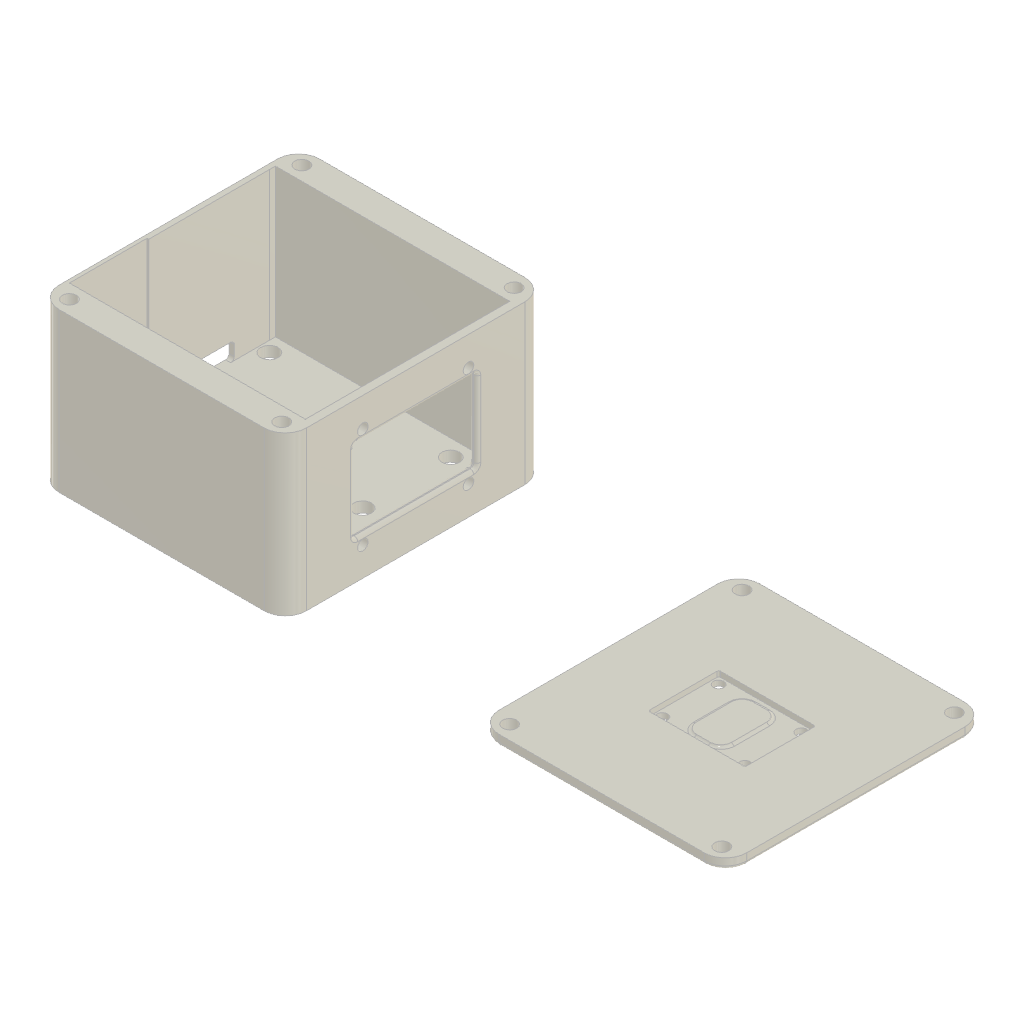
desktop_pet_housing (Autodesk Fusion 360 design; units mm, degrees)
part number: 2026-10-13-15-29-51-943
Autodesk Fusion 360 part; units mm, degrees
sketch "Sketch1" plane through (0, 0, 0) normal (0, 0, 1) x (1, 0, 0)
  line L0 (49.9787, 99.2431) -> (107.4787, 99.2431)
  line L1 (107.4787, 99.2431) -> (107.4787, 68.2431)
  line L2 (107.4787, 68.2431) -> (49.9787, 68.2431)
  line L3 (49.9787, 68.2431) -> (49.9787, 99.2431)
  line L4 (49.9787, 99.2431) -> (49.9787, 96.2431) construction
  line L5 (49.9787, 96.2431) -> (52.9787, 96.2431) construction
  line L6 (49.9787, 68.2431) -> (52.9787, 68.2431) construction
  line L7 (52.9787, 68.2431) -> (52.9787, 71.2431) construction
  line L8 (107.4787, 68.2431) -> (107.4787, 71.2431) construction
  line L9 (107.4787, 71.2431) -> (104.4787, 71.2431) construction
  line L10 (107.4787, 99.2431) -> (107.4787, 96.2431) construction
  line L11 (107.4787, 96.2431) -> (104.4787, 96.2431) construction
  circle A0 centre (52.9787, 96.2431) radius 2.5
  circle A1 centre (52.9787, 71.2431) radius 2.5
  circle A2 centre (104.4787, 71.2431) radius 2.5
  circle A3 centre (104.4787, 96.2431) radius 2.5
  line L12 (51.4787, 78.7555) -> (48.4787, 78.7555)
  line L13 (48.4787, 78.7555) -> (48.4787, 89.2555)
  line L14 (48.4787, 89.2555) -> (51.4787, 89.2555)
  line L15 (51.4787, 89.2555) -> (51.4787, 78.7555)
  line L16 (51.4787, 78.7555) -> (48.4787, 89.2555) construction
  line L17 (48.4787, 78.7555) -> (51.4787, 89.2555) construction
  line L18 (52.9787, 71.2431) -> (49.9787, 71.2431) construction
  line L19 (52.9787, 96.2431) -> (52.9787, 99.2431) construction
  line L20 (104.4787, 71.2431) -> (104.4787, 68.2431) construction
  line L21 (104.4787, 96.2431) -> (104.4787, 99.2431) construction
  line L22 (61.5, 44) -> (49.5, 44)
  line L23 (61.5, 65) -> (61.5, 44)
  circle A4 centre (51.5, 46) radius 1.6
  line L24 (50.5, 50.75) -> (50.5, 59.25)
  circle A5 centre (51.5, 63) radius 1.6
  line L25 (49.5, 65) -> (61.5, 65)
  line L26 (50.5, 59.25) -> (48.5, 59.25)
  line L27 (48.5, 50.75) -> (50.5, 50.75)
  line L28 (49.5, 44) -> (49.5, 65)
  line L29 (48.5, 50.75) -> (48.5, 59.25)
  line L30 (51.5, 46) -> (51.5, 44) construction
  line L31 (51.5, 46) -> (49.5, 46) construction
  line L32 (51.5, 63) -> (51.5, 65) construction
  line L33 (51.5, 63) -> (49.5, 63) construction
  line L34 (107.5, 65) -> (65.5, 65)
  line L35 (65.5, 65) -> (65.5, 45)
  line L36 (65.5, 45) -> (107.5, 45)
  line L37 (107.5, 45) -> (107.5, 65)
  line L38 (65.5, 65) -> (75.5, 65) construction
  circle A6 centre (75.5, 65) radius 1.5
  line L39 (75.5, 65) -> (75.5, 45) construction
  circle A7 centre (75.5, 45) radius 1.5
  line L40 (48.5, 42.9562) -> (116.5, 42.9562)
  line L41 (116.5, 42.9562) -> (116.5, 100.9562)
  line L42 (116.5, 100.9562) -> (48.5, 100.9562)
  line L43 (48.5, 100.9562) -> (48.5, 42.9562)
  line L44 (116.5, 42.9562) -> (113.7862, 42.9562) construction
  line L45 (48.5, 42.9562) -> (53.5, 42.9562) construction
  line L46 (116.5, 42.9562) -> (113.7862, 42.9562) construction
  line L47 (116.5, 100.9562) -> (113.7862, 100.9562) construction
  line L48 (48.5, 100.9562) -> (53.5, 100.9562) construction
  line L49 (113.7862, 42.9562) -> (113.7862, 38.9562) construction
  line L50 (53.5, 42.9562) -> (53.5, 38.9562) construction
  line L51 (53.5, 100.9562) -> (53.5, 104.9562) construction
  line L52 (113.7862, 100.9562) -> (113.7862, 104.9562) construction
  circle A8 centre (113.7862, 104.9562) radius 2
  circle A9 centre (53.5, 104.9562) radius 2
  circle A10 centre (53.5, 38.9562) radius 2
  circle A11 centre (113.7862, 38.9562) radius 2
  line L53 (48.5, 34.9615) -> (118.7862, 34.9615)
  line L54 (118.7862, 34.9615) -> (118.7862, 109)
  line L55 (118.7862, 109) -> (48.5, 109)
  line L56 (48.5, 109) -> (48.5, 34.9615)
  line L57 (173.5, 42.9562) -> (178.5, 42.9562) construction
  circle A12 centre (178.5, 38.9562) radius 2
  line L58 (178.5, 100.9562) -> (178.5, 104.9562) construction
  line L59 (233.5, 42.9562) -> (233.5, 100.9562)
  line L60 (178.5, 42.9562) -> (178.5, 38.9562) construction
  line L61 (243.786, 109) -> (173.5, 109)
  line L62 (233.5, 100.9562) -> (238.786, 100.9562) construction
  circle A13 centre (178.5, 104.9562) radius 2
  line L63 (173.5, 100.9562) -> (178.5, 100.9562) construction
  line L64 (173.5, 100.9562) -> (173.5, 42.9562)
  line L65 (173.5, 109) -> (173.5, 34.9615)
  line L66 (233.5, 100.9562) -> (173.5, 100.9562)
  line L67 (238.786, 100.9562) -> (238.786, 104.9562) construction
  line L68 (173.5, 34.9615) -> (243.786, 34.9615)
  circle A14 centre (238.786, 104.9562) radius 2
  line L69 (228.5, 42.9562) -> (228.5, 38.9562) construction
  line L70 (173.5, 42.9562) -> (233.5, 42.9562)
  line L71 (243.786, 34.9615) -> (243.786, 109)
  line L72 (233.5, 42.9562) -> (228.5, 42.9562) construction
  line L73 (233.5, 42.9562) -> (228.5, 42.9562) construction
  line L74 (243.786, 34.9615) -> (243.786, 71.9807) construction
  line L75 (243.786, 71.9807) -> (208.6431, 71.9156) construction
  line L76 (194.8931, 81.9156) -> (222.3931, 81.9156)
  line L77 (222.3931, 81.9156) -> (222.3931, 61.9156)
  line L78 (222.3931, 61.9156) -> (194.8931, 61.9156)
  line L79 (194.8931, 61.9156) -> (194.8931, 81.9156)
  line L80 (194.8931, 81.9156) -> (222.3931, 61.9156) construction
  line L81 (222.3931, 81.9156) -> (194.8931, 61.9156) construction
  line L82 (194.8931, 81.9156) -> (194.8931, 79.9156) construction
  line L83 (194.8931, 79.9156) -> (196.8931, 79.9156) construction
  line L84 (194.8931, 61.9156) -> (194.8931, 63.9156) construction
  line L85 (194.8931, 63.9156) -> (196.8931, 63.9156) construction
  line L86 (222.3931, 81.9156) -> (220.3931, 81.9156) construction
  line L87 (220.3931, 81.9156) -> (220.3931, 79.9156) construction
  line L88 (222.3931, 61.9156) -> (212, 61.9156) construction
  line L89 (222.3931, 61.9156) -> (222.3931, 63.9156) construction
  line L90 (222.3931, 63.9156) -> (220.3931, 63.9156) construction
  circle A15 centre (220.3931, 63.9156) radius 1.5
  circle A16 centre (220.3931, 79.9156) radius 1.5
  circle A17 centre (196.8931, 79.9156) radius 1.5
  circle A18 centre (196.8931, 63.9156) radius 1.5
  line L91 (203.4731, 63.9963) -> (213.4731, 63.9963)
  line L92 (213.4731, 63.9963) -> (213.4731, 79.9963)
  line L93 (213.4731, 79.9963) -> (203.4731, 79.9963)
  line L94 (203.4731, 79.9963) -> (203.4731, 63.9963)
  line L95 (49.9787, 99.2431) -> (49.9792, 100.9562)
  line L96 (49.9787, 68.2431) -> (49.9787, 65)
  line L97 (49.5, 44) -> (49.5, 42.9561)
  line L98 (113.7862, 38.9562) -> (118.7862, 38.9562) construction
  line L99 (113.7862, 104.9562) -> (118.7862, 104.9562) construction
  line L100 (228.5, 38.9562) -> (243.786, 38.9498) construction
  line L101 (238.786, 104.9562) -> (243.786, 104.9562) construction
  line L102 (238.786, 104.9562) -> (238.7585, 38.9519) construction
  circle A19 centre (238.7585, 38.9519) radius 2
  line L103 (49.9787, 68.2431) -> (49.9787, 83.7431) construction
  point P0 (49.9787, 84.0055)
  point P1 (208.6431, 71.9156)
  dimension "d1" = 57.5
  dimension "d2" = 31
  dimension "d10" = 3
  dimension "d14" = 5
  dimension "d15" = 3
  dimension "d16" = 10.5
  dimension "d17" = 12
  dimension "d18" = 21
  dimension "d20" = 3.2
  dimension "d21" = 2
  dimension "d22" = 8.5
  dimension "d23" = 2
  dimension "d31" = 42
  dimension "d32" = 20
  dimension "d33" = 10
  dimension "d34" = 3
  dimension "d35" = 3
  dimension "d36" = 68
  dimension "d37" = 58
  dimension "d39" = 5
  dimension "d41" = 5
  dimension "d42" = 4
  dimension "d43" = 4
  dimension "d44" = 4
  dimension "d45" = 4
  dimension "d46" = 4
  dimension "d47" = 4
  dimension "d48" = 4
  dimension "d49" = 4
  dimension "d67" = 60
  dimension "d68" = 58
  dimension "d70" = 5
  dimension "d72" = 5
  dimension "d73" = 4
  dimension "d74" = 4
  dimension "d75" = 4
  dimension "d76" = 4
  dimension "d77" = 4
  dimension "d78" = 4
  dimension "d79" = 4
  dimension "d81" = 74.0385
  dimension "d82" = 27.5
  dimension "d83" = 20
  dimension "d84" = 2
  dimension "d85" = 2
  dimension "d86" = 2
  dimension "d87" = 2
  dimension "d88" = 2
  dimension "d89" = 2
  dimension "d90" = 3
  dimension "d91" = 3
  dimension "d92" = 3
  dimension "d93" = 3
  dimension "d150" = 35.143
  dimension "d151" = 70.286
  dimension "d152" = 2
  dimension "d153" = 2
  dimension "d154" = 16
  dimension "d155" = 10
  dimension "d156" = 5
  dimension "d157" = 5
  dimension "d158" = 70.2862
  dimension "d159" = 74.0385
  dimension "d160" = 5
  dimension "d161" = 15.286
  dimension "d162" = 4
  dimension "d163" = 3
  dimension "d164" = 3
  dimension "d165" = 3
  constraint horizontal L0
  constraint vertical L1
  constraint horizontal L2
  constraint vertical L3
  constraint perpendicular L0 L4
  constraint perpendicular L3 L5
  constraint perpendicular L3 L6
  constraint perpendicular L6 L7
  constraint perpendicular L2 L8
  constraint perpendicular L1 L9
  constraint coincident L1 L10.end
  constraint perpendicular L10 L11
  constraint coincident L5.end A0.centre
  constraint coincident L7.end A1.centre
  constraint coincident L9.end A2.centre
  constraint coincident L11.end A3.centre
  constraint horizontal L12
  constraint perpendicular L12 L13
  constraint parallel L12 L14
  constraint parallel L13 L15
  constraint coincident L16 P0
  constraint coincident L17 P0
  constraint coincident L3 P0
  constraint equal A2 A3
  constraint equal A0 A3
  constraint equal A0 A1
  constraint coincident L3 L18.end
  constraint perpendicular L3 L18
  constraint coincident L0 L19.end
  constraint perpendicular L0 L19
  constraint coincident L2 L20.end
  constraint perpendicular L2 L20
  constraint coincident L0 L21.end
  constraint perpendicular L0 L21
  constraint equal L11 L21
  constraint equal L9 L20
  constraint equal L7 L18
  constraint equal L5 L19
  constraint perpendicular L24 L27
  constraint parallel L26 L27
  constraint perpendicular L26 L29
  constraint coincident A4.centre L30.start
  constraint coincident L22 L30.end
  constraint perpendicular L22 L30
  constraint coincident L28 L31.end
  constraint perpendicular L28 L31
  constraint coincident A5.centre L32.start
  constraint coincident L25 L32.end
  constraint perpendicular L25 L32
  constraint coincident L28 L33.end
  constraint perpendicular L28 L33
  constraint equal A4 A5
  constraint equal L32 L33
  constraint equal L30 L31
  constraint horizontal L34
  constraint vertical L35
  constraint horizontal L36
  constraint vertical L37
  constraint perpendicular L35 L38
  constraint coincident L38.end A6.centre
  constraint coincident L36 L39.end
  constraint perpendicular L36 L39
  constraint coincident L39.end A7.centre
  constraint horizontal L40
  constraint vertical L41
  constraint horizontal L42
  constraint vertical L43
  constraint coincident L40 L44.end
  constraint coincident L40 L45.end
  constraint coincident L42 L47.end
  constraint coincident L42 L48.end
  constraint perpendicular L46 L49
  constraint perpendicular L45 L50
  constraint perpendicular L42 L51
  constraint perpendicular L47 L52
  constraint coincident L52.end A8.centre
  constraint coincident L51.end A9.centre
  constraint coincident L50.end A10.centre
  constraint coincident L49.end A11.centre
  constraint horizontal L53
  constraint vertical L54
  constraint horizontal L55
  constraint vertical L56
  constraint horizontal L70
  constraint vertical L59
  constraint horizontal L66
  constraint vertical L64
  constraint coincident L69.start L70
  constraint coincident L57.end L70
  constraint coincident L62.end L66
  constraint coincident L58.start L66
  constraint perpendicular L69 L73
  constraint perpendicular L57 L60
  constraint perpendicular L58 L66
  constraint perpendicular L62 L67
  constraint coincident L67.end A14.centre
  constraint coincident L58.end A13.centre
  constraint coincident A12.centre L60.end
  constraint horizontal L68
  constraint vertical L71
  constraint horizontal L61
  constraint vertical L65
  constraint midpoint L71 L74.end
  constraint horizontal L76
  constraint perpendicular L76 L77
  constraint parallel L76 L78
  constraint parallel L77 L79
  constraint coincident L80 P1
  constraint coincident L81 P1
  constraint coincident P1 L75.end
  constraint perpendicular L76 L82
  constraint perpendicular L82 L83
  constraint coincident L79 L84.end
  constraint perpendicular L79 L85
  constraint coincident L76 L86.end
  constraint perpendicular L86 L87
  constraint coincident L78 L88.end
  constraint coincident L77 L89.end
  constraint perpendicular L77 L90
  constraint coincident L90.end A15.centre
  constraint coincident L87.end A16.centre
  constraint coincident L83.end A17.centre
  constraint coincident L85.end A18.centre
  constraint horizontal L91
  constraint vertical L92
  constraint horizontal L93
  constraint vertical L94
  constraint coincident L48 L95.end
  constraint coincident L25 L96.end
  constraint perpendicular L25 L96
  constraint vertical L97
  constraint coincident L54 L98.end
  constraint perpendicular L54 L98
  constraint coincident L54 L99.end
  constraint perpendicular L54 L99
  constraint coincident L74 L100.end
  constraint coincident L71 L101.end
  constraint perpendicular L71 L101
  constraint coincident L100 L102.end
  constraint perpendicular L100 L102
  constraint coincident L102.end A19.centre
  constraint midpoint L3 L103.end
  measures "d1" distance of L0.start L0.end
  measures "d2" distance of L0.start L2.end
  measures "d10" distance of L0.end L10.end
  measures "d14" diameter of A3
  measures "d15" distance of L13.end L14.end
  measures "d16" distance of L12.end L13.end
  measures "d17" distance of L22.start L22.end
  measures "d18" distance of L22.start L23.start
  measures "d20" diameter of A5
  measures "d21" distance of L24.end L26.end
  measures "d22" distance of L24.start L24.end
  measures "d23" distance of A5.centre L32.end
  measures "d31" distance of L34.start L34.end
  measures "d32" distance of L34.start L36.end
  measures "d33" distance of L34.end L38.end
  measures "d34" diameter of A6
  measures "d35" diameter of A7
  measures "d36" distance of L40.start L40.end
  measures "d37" distance of L40.start L42.end
  measures "d39" distance of L40.start L45.end
  measures "d41" distance of L42.end L48.end
  measures "d42" distance of L44.end L49.end
  measures "d43" distance of L45.end L50.end
  measures "d44" distance of L48.end L51.end
  measures "d45" distance of L47.end L52.end
  measures "d46" diameter of A8
  measures "d47" diameter of A9
  measures "d48" diameter of A10
  measures "d49" diameter of A11
  measures "d67" distance of L57.start L59.start
  measures "d68" distance of L63.start L57.start
  measures "d70" distance of L57.start L57.end
  measures "d72" distance of L63.start L58.start
  measures "d73" distance of L69.start L69.end
  measures "d74" distance of L57.end A12.centre
  measures "d75" distance of L58.start L58.end
  measures "d76" distance of L62.end L67.end
  measures "d77" diameter of A14
  measures "d78" diameter of A13
  measures "d79" diameter of A12
  measures "d81" distance of L61.start L68.end
  measures "d82" distance of L77.end L78.end
  measures "d83" distance of L76.end L77.end
  measures "d84" distance of L76.start L82.end
  measures "d85" distance of L78.end L84.end
  measures "d86" distance of L84.end L85.end
  measures "d87" distance of L76.end L86.end
  measures "d88" distance of L86.end L87.end
  measures "d89" distance of L77.end L89.end
  measures "d90" diameter of A15
  measures "d91" diameter of A16
  measures "d92" diameter of A17
  measures "d93" diameter of A18
  measures "d150" distance of L74.end P1
  measures "d151" distance of L65.end L68.end
  measures "d152" distance of L82.end L83.end
  measures "d153" distance of L89.end L90.end
  measures "d154" distance of L91.start L93.end
  measures "d155" distance of L92.end L93.end
  measures "d156" distance of L49.end L98.end
  measures "d157" distance of L52.end L99.end
  measures "d158" distance of L54.end L55.end
  measures "d159" distance of L53.end L54.end
  measures "d160" distance of L67.end L101.end
  measures "d161" horizontal distance of L69.end L100.end
  measures "d162" diameter of A19
  measures "d163" distance of L7.end L18.end
  measures "d164" distance of L5.end L19.end
  measures "d165" distance of L9.end L20.end
extrude "Extrude1" add sketch "Sketch1" along normal blind 45 contours L3 L14 L42 L43 L56 L95 | L40 L41 L42 L53 L54 L55 L56 | L3 L12 L25 L26 L28 L43 L56 L96 | L27 L28 L40 L43 L56 L97 makes body 1 at (118.7862, 59.641, 30) makes body 2 at (48.5, 72.2537, 15)
extrude "Extrude2" add sketch "Sketch1" along normal blind 3 contours L0 L1 L2 L22 L23 L25 L40 L41 L42 L95 L96 L97 | L0 L1 L2 L3 L12 L14 L15 | L3 L12 L14 L15 | L3 L12 L14 L43 L56 | L22 L23 L24 L25 L26 L27 L28 | L26 L27 L28 L29 L43 L56 | L24 L26 L27 L28 | L34 L35 L36 L37 A6 A7 bodies 1 2
extrude "Extrude3" add sketch "Sketch1" along normal blind 3 contours L26 L27 L28 L29 L43 L56 bodies 1
extrude "Extrude4" add sketch "Sketch1" along normal blind 37 from surface at 8 contours L26 L27 L28 L29 L43 L56 bodies 1
extrude "Extrude5" add sketch "Sketch1" along normal blind 37 from surface at 8 contours L3 L12 L14 L43 L56 | L12 L13 L14 L43 L56 bodies 1
extrude "Extrude6" add sketch "Sketch1" along normal blind 3 separate body contours L59 L64 L65 L66 L70 | L59 L61 L65 L66 L68 L70 L71 makes body 3
extrude "Extrude7" add sketch "Sketch1" along normal blind 1.5 and the other way blind 0 contours L76 L77 L78 L79 bodies 3
extrude "Extrude8" add sketch "Sketch1" along normal blind 2 contours L91 L92 L93 L94 bodies 3
sketch "Sketch2" plane through (118.7862, 0, 0) normal (1, 0, 0) x (0, 1, 0)
  line L0 (34.9615, 0) -> (109, 0)
  line L1 (109, 0) -> (109, 45)
  line L2 (109, 45) -> (34.9615, 45)
  line L3 (34.9615, 45) -> (34.9615, 0)
  line L4 (34.9615, 45) -> (109, 0) construction
  line L5 (34.9615, 0) -> (109, 45) construction
  line L6 (89.4807, 5.75) -> (54.4807, 5.75)
  line L7 (54.4807, 5.75) -> (54.4807, 39.25)
  line L8 (54.4807, 39.25) -> (89.4807, 39.25)
  line L9 (89.4807, 39.25) -> (89.4807, 5.75)
  line L10 (89.4807, 5.75) -> (54.4807, 39.25) construction
  line L11 (54.4807, 5.75) -> (89.4807, 39.25) construction
  line L12 (89.4807, 39.25) -> (89.4807, 36.75) construction
  line L13 (89.4807, 36.75) -> (86.9807, 36.75) construction
  line L14 (54.4807, 39.25) -> (54.4807, 36.75) construction
  line L15 (54.4807, 36.75) -> (56.9807, 36.75) construction
  line L16 (54.4807, 5.75) -> (56.9807, 5.75) construction
  line L17 (56.9807, 5.75) -> (56.9807, 8.25) construction
  line L18 (89.4807, 5.75) -> (86.9807, 5.75) construction
  line L19 (86.9807, 5.75) -> (86.9807, 8.25) construction
  circle A0 centre (86.9807, 8.25) radius 1.5
  circle A1 centre (56.9807, 8.25) radius 1.5
  circle A2 centre (56.9807, 36.75) radius 1.5
  circle A3 centre (86.9807, 36.75) radius 1.5
  line L20 (54.4807, 39.25) -> (54.4807, 34.25)
  line L21 (54.4807, 5.75) -> (54.4807, 10.75)
  line L22 (54.4807, 10.75) -> (89.4807, 10.75)
  line L23 (54.4807, 34.25) -> (89.4807, 34.25)
  point P0 (71.9807, 22.5)
  dimension "d114" = 35
  dimension "d115" = 33.5
  dimension "d116" = 2.5
  dimension "d117" = 2.5
  dimension "d118" = 2.5
  dimension "d119" = 2.5
  dimension "d120" = 2.5
  dimension "d121" = 2.5
  dimension "d122" = 2.5
  dimension "d123" = 2.5
  dimension "d124" = 3
  dimension "d125" = 3
  dimension "d126" = 3
  dimension "d127" = 3
  dimension "d128" = 5
  dimension "d129" = 5
  constraint coincident L2.end L3.start
  constraint coincident L0.end L1.start
  constraint coincident L0.start L3.end
  constraint coincident L1.end L2.start
  constraint horizontal L6
  constraint perpendicular L6 L7
  constraint parallel L6 L8
  constraint parallel L7 L9
  constraint coincident L10 P0
  constraint coincident L11 P0
  constraint midpoint L5 P0
  constraint perpendicular L8 L12
  constraint perpendicular L9 L13
  constraint perpendicular L8 L14
  constraint perpendicular L7 L15
  constraint perpendicular L7 L16
  constraint perpendicular L6 L17
  constraint perpendicular L9 L18
  constraint perpendicular L18 L19
  constraint coincident L19.end A0.centre
  constraint coincident L17.end A1.centre
  constraint coincident L15.end A2.centre
  constraint coincident L13.end A3.centre
  constraint perpendicular L8 L20
  constraint perpendicular L16 L21
  constraint coincident L9 L22.end
  constraint perpendicular L9 L22
  constraint coincident L9 L23.end
  constraint perpendicular L9 L23
  measures "d114" distance of L7.end L8.end
  measures "d115" distance of L6.end L7.end
  measures "d116" distance of L8.end L12.end
  measures "d117" distance of L12.end L13.end
  measures "d118" distance of L7.end L14.end
  measures "d119" distance of L14.end L15.end
  measures "d120" distance of L6.end L16.end
  measures "d121" distance of L16.end L17.end
  measures "d122" distance of L6.start L18.end
  measures "d123" distance of L18.end L19.end
  measures "d124" diameter of A0
  measures "d125" diameter of A1
  measures "d126" diameter of A2
  measures "d127" diameter of A3
  measures "d128" distance of L7.end L20.end
  measures "d129" distance of L6.end L21.end
extrude "Extrude9" cut sketch "Sketch2" against normal blind 9 contours L7 L9 L22 L23 | A0 | A1 | A2 | A3 bodies 1
fillet "Fillet1" radius 6 8 edges at (118.7862, 109, 22.5) (118.7862, 34.9615, 22.5) (48.5, 109, 22.5) (48.5, 34.9615, 22.5) (173.5, 109, 1.5) (243.786, 109, 1.5) (243.786, 34.9615, 1.5) (173.5, 34.9615, 1.5) on bodies 1 3
fillet "Fillet2" radius 1 20 edges at (118.7862, 71.9807, 34.25) (118.7862, 54.4807, 22.5) (118.7862, 71.9807, 10.75) (118.7862, 89.4807, 22.5) (117.6431, 54.4807, 34.25) (117.6431, 89.4807, 34.25) (117.6431, 89.4807, 10.75) (117.6431, 54.4807, 10.75) (116.5, 71.9807, 10.75) (116.5, 54.4807, 22.5) (116.5, 71.9807, 34.25) (116.5, 89.4807, 22.5) (49, 50.75, 8) (49, 59.25, 8) (49, 50.75, 3) (49, 59.25, 3) (49.2394, 78.7555, 3) (49.2394, 89.2555, 3) (49.2394, 89.2555, 8) (49.2394, 78.7555, 8) on bodies 1
fillet "Fillet4" radius 0.5 4 edges at (222.3931, 61.9156, 2.25) (222.3931, 81.9156, 2.25) (194.8931, 81.9156, 2.25) (194.8931, 61.9156, 2.25) on bodies 3
fillet "Fillet5" radius 3 4 edges at (213.4731, 63.9963, 1.75) (213.4731, 79.9963, 1.75) (203.4731, 79.9963, 1.75) (203.4731, 63.9963, 1.75) on bodies 3
fillet "Fillet6" radius 1 8 edges at (208.4731, 63.9963, 1.5) (212.5944, 64.875, 1.5) (213.4731, 71.9963, 1.5) (212.5944, 79.1177, 1.5) (208.4731, 79.9963, 1.5) (204.3517, 79.1177, 1.5) (203.4731, 71.9963, 1.5) (204.3517, 64.875, 1.5) on bodies 3
fillet "Fillet7" [no effect]
fillet "Fillet8" [no effect]
fillet "Fillet9" radius 1 8 edges at (208.643, 34.9615, 0) (242.0286, 36.7188, 0) (243.786, 71.9807, 0) (242.0286, 107.2426, 0) (208.643, 109, 0) (175.2574, 107.2426, 0) (173.5, 71.9807, 0) (175.2574, 36.7188, 0) on bodies 3
